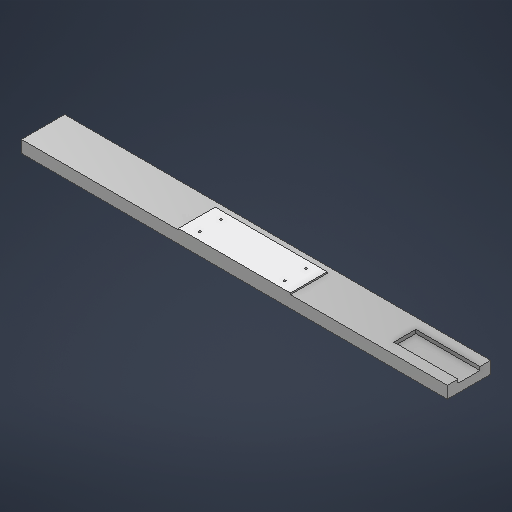
# Autodesk Inventor part: Pantalla_v0
Saved by Autodesk Inventor 2027 (Build 310192060, 192F)
## iProperties
Created: 2026-10-11
Part Number: Pantalla_v0
Material: Generic
Document SubType Name: Modeling
Designer: Pablo
Density: 1 g/cm^3
Appearance: Default
Author: Pablo
Autodesk Inventor part; units mm, degrees
ref_plane "YZ Plane" through (0, 0, 0) normal (1, 0, 0) x (0, 1, 0)
ref_plane "XZ Plane" through (0, 0, 0) normal (0, 1, 0) x (-1, 0, 0)
sketch "Sketch1" plane through (0, 0, 0) normal (0, 1, 0) x (-1, 0, 0)
  line L0 (-79, 26) -> (79, 26)
  line L1 (79, 26) -> (79, -26)
  line L2 (79, -26) -> (-79, -26)
  line L3 (-79, -26) -> (-79, 26)
  line L4 (-79, 26) -> (79, -26) construction
  line L5 (79, 26) -> (-79, -26) construction
  line L6 (300.5, 26) -> (-300.5, 26)
  line L7 (-300.5, 26) -> (-300.5, -35)
  line L8 (-300.5, -35) -> (300.5, -35)
  line L9 (300.5, -35) -> (300.5, 26)
  line L10 (0, 284.2539) -> (0, -284.2539)
  line L11 (-222.6051, 0) -> (222.6051, 0)
  point P0 (0, 0)
  dimension "d0" = 158
  dimension "d1" = 601
  dimension "d2" = 52
  dimension "d3" = 9
  constraints: 24 end point, 4 midpoint, 4 parallel, 3 horizontal, 2 perpendicular, 1 collinear, 1 vertical, 1 other
  measures "d0" distance of L1.end L2.end
  measures "d1" distance between parallel lines of L7 L9
  measures "d2" distance between parallel lines of L0 L2
  measures "d3" distance between parallel lines of L8 L2
extrude "Extrusion1" add sketch "Sketch1" along normal blind 2 contours L0 L10 L11 L3 | L0 L1 L11 L10 | L11 L10 L2 L3 | L11 L1 L2 L10
extrude "Extrusion2" add sketch "Sketch1" against normal blind 17
sketch "Sketch2" plane through (0, 2, 0) normal (0, 1, 0) x (1, 0, 0)
  circle A0 centre (-60, -15) radius 1.5
  line L0 (0, -73.8528) -> (0, 73.8528)
  line L1 (76.7139, 0) -> (-76.7139, 0)
  circle A1 centre (-60, 15) radius 1.5
  circle A2 centre (60, -15) radius 1.5
  circle A3 centre (60, 15) radius 1.5
  point P0 (0, 0)
  dimension "d8" = 3
  dimension "d11" = 30
  dimension "d14" = 120
  constraints: 4 centre point, 4 end point, 2 horizontal, 2 midpoint, 2 symmetric about line, 2 vertical, 6 other
  measures "d8" diameter of A0
  measures "d11" distance of A0.centre A1.centre
  measures "d14" distance of A0.centre A2.centre
extrude "Extrusion3" cut sketch "Sketch2" against normal blind 2
sketch "Sketch3" plane through (0, 0, 0) normal (0, 1, 0) x (1, 0, 0)
  line L0 (300.5, -26) -> (300.5, 35) projected
  line L1 (300.5, -11) -> (209.9837, -11)
  line L2 (209.9837, -11) -> (209.9837, 20)
  line L3 (209.9837, 20) -> (300.5, 20)
  line L4 (-235.1975, 0) -> (235.1975, 0)
  line L5 (-300.5, -26) -> (300.5, -26) construction
  line L6 (300.5, 35) -> (-300.5, 35) construction
  point P0 (0, 0)
  dimension "d19" = 15
  dimension "d20" = 15
  constraints: 8 end point, 2 horizontal, 2 perpendicular, 2 point on line, 1 midpoint
  measures "d19" distance between parallel lines of L5 L1
  measures "d20" distance between parallel lines of L6 L3
extrude "Extrusion4" cut sketch "Sketch3" against normal blind 5
ref_plane "Work Plane1" through (0, -17, -4.5) normal (0, 0, 1) x (1, 0, 0)
body "Solid1"
